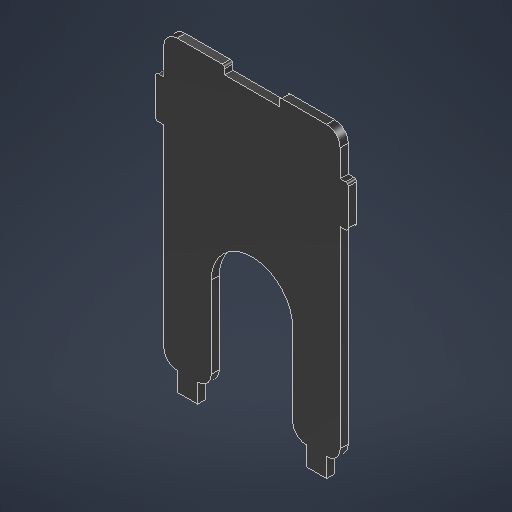
# Autodesk Inventor part: SlotSide
Saved by Autodesk Inventor 2027.1 (Build 311270010, 270A)
## iProperties
Created: 2026-10-20
Part Number: SlotSide
Material: MDF Medium Density Fiberboard
Document SubType Name: Modeling
Designer: SDS Scholar
Density: 0.8 g/cm^3
Appearance: Glossy - Black
Mass: 13.1637 g
Surface Area: 122.648 cm^2
Volume: 16.4547 cm^3
Author: SDS Scholar
Autodesk Inventor part; units mm, degrees
ref_plane "YZ Plane" through (0, 0, 0) normal (1, 0, 0) x (0, 1, 0)
ref_plane "XZ Plane" through (0, 0, 0) normal (0, 1, 0) x (-1, 0, 0)
ref_plane "XY Plane" through (0, 0, 0) normal (0, 0, 1) x (1, 0, 0)
sketch "Sketch1" plane through (0, 0, 0) normal (0, 0, 1) x (1, 0, 0)
  line L0 (-32.5, 53) -> (32.5, 53)
  line L1 (32.5, 53) -> (32.5, -53)
  line L2 (32.5, -53) -> (-32.5, -53)
  line L3 (-32.5, -53) -> (-32.5, 53)
  line L4 (-10, 53) -> (10, 53)
  line L5 (10, 53) -> (10, 50)
  line L6 (10, 50) -> (-10, 50)
  line L7 (-10, 50) -> (-10, 53)
  line L8 (-32.5, 8) -> (32.5, 8) construction
  line L9 (0, 53) -> (0, 8) construction
  line L10 (0, 8) -> (0, -53) construction
  line L11 (-32.5, 38.15) -> (-35.5, 38.15)
  line L12 (-35.5, 38.15) -> (-35.5, 22.85)
  line L13 (-35.5, 22.85) -> (-32.5, 22.85)
  line L14 (-32.5, 22.85) -> (-32.5, 38.15)
  line L15 (32.5, 38.15) -> (35.5, 38.15)
  line L16 (35.5, 38.15) -> (35.5, 22.85)
  line L17 (35.5, 22.85) -> (32.5, 22.85)
  line L18 (-32.5, -18) -> (32.5, -18) construction
  line L19 (-15, -53) -> (-15, -18)
  line L20 (15, -53) -> (15, -18)
  arc A0 (15, -18) -> (-15, -18) centre (0, -18) ccw
  point P0 (0, 0)
  point P1 (32.5, 0)
  point P2 (0, 50)
  point P3 (0, 0)
  point P4 (0, 30.5)
  point P5 (-35.5, 30.5)
  dimension "d0" = 65
  dimension "d1" = 106
  dimension "d10" = 20
  dimension "d11" = 3
  dimension "d12" = 45
  dimension "d13" = 45
  dimension "d16" = 3
  dimension "d17" = 15.3
  dimension "d18" = 35
  dimension "d19" = 30
  dimension "d20" = 15
  constraints: 42 end point, 10 point on line, 7 midpoint, 7 parallel, 5 perpendicular, 4 horizontal, 4 symmetric about line, 2 horizontal alignment, 2 point on circle, 1 centre point, 1 coincident, 1 vertical alignment, 1 other
  measures "d0" distance of L1.end L2.end
  measures "d1" distance of L0.end L1.end
  measures "d10" distance of L5.end L6.end
  measures "d11" distance of L6.end L4.start
  measures "d12" distance between parallel lines of L8 L0
  measures "d13" distance of L9.start L9.end
  measures "d16" distance of L11.start L11.end
  measures "d17" distance of L11.end L12.end
  measures "d18" distance between parallel lines of L2 L18
  measures "d19" distance between parallel lines of L20 L19
  measures "d20" radius of A0
extrude "Extrusion1" add sketch "Sketch1" along normal blind 3 contours L0 L7 L6 L5 L1 L2 L20 A0 L19 L3 | L3 L13 L12 L11 | L15 L16 L17 L1
fillet "Fillet1" radius 5 6 edges at (32.5, 53, 1.5) (-32.5, 53, 1.5) (32.5, -53, 1.5) (-32.5, -53, 1.5) (15, -53, 1.5) (-15, -53, 1.5)
fillet "Fillet2" radius 1 6 edges at (-10, 53, 1.5) (10, 53, 1.5) (35.5, 38.15, 1.5) (35.5, 22.85, 1.5) (-35.5, 38.15, 1.5) (-35.5, 22.85, 1.5)
sketch "Sketch2" plane through (0, 0, 3) normal (0, 0, 1) x (1, 0, 0)
  line L0 (-27.5, -53) -> (-20, -53) projected
  line L1 (-27.5, -53) -> (-20, -53)
  line L2 (-20, -53) -> (-20, -60)
  line L3 (-20, -60) -> (-27.5, -60)
  line L4 (-27.5, -60) -> (-27.5, -53)
  line L5 (10, 50) -> (-10, 50) projected
  line L6 (0, 50) -> (0, -3) construction
  arc A0 (15, -18) -> (-15, -18) centre (0, -18) ccw projected
  line L7 (27.5, -53) -> (20, -53)
  line L8 (27.5, -53) -> (20, -53)
  line L9 (20, -53) -> (20, -60)
  line L10 (20, -60) -> (27.5, -60)
  line L11 (27.5, -60) -> (27.5, -53)
  point P0 (0, 0)
  dimension "d21" = 7
  dimension "d22" = 7.5
  constraints: 20 end point, 5 symmetric about line, 2 parallel, 1 horizontal, 1 midpoint, 1 perpendicular, 1 point on circle, 1 vertical
  measures "d21" distance of L1.end L2.end
  measures "d22" distance of L2.end L3.end
extrude "Extrusion2" add sketch "Sketch2" against normal blind 3
equation "\"d12\" = ProductTotalHeight"
equation "\"GridProcutClearance\" = 5"
equation "\"GridBorderThickness\" = 5"
equation "\"GridBorderFillets\" = 7"
equation "\"GridTotalSize\" = 65"
equation "\"GridRobotClearance\" = 65"
equation "\"AluminiumExtrusionClearance\" = 35"
equation "\"BaseTotalLength\" = 885"
equation "\"WorkspaceLength\" = 515"
equation "\"WorkspaceHeight\" = 183"
equation "\"AxesBaseFillet\" = 15"
equation "\"Zaxis\" = 197"
equation "\"ProductTotalHeight\" = 45"
equation "\"VerticalStroke\" = 105"
equation "\"BackArea\" = 165"
equation "\"CylinderStroke\" = 75"
equation "\"BoxesWidth\" = 125"
equation "\"BaseWoodThickness\" = 7"
equation "\"Kerf\" = 0.3"
equation "\"RxThickness\" = 1.8"
equation "\"support_2\" = 265"
body "Solid1"
